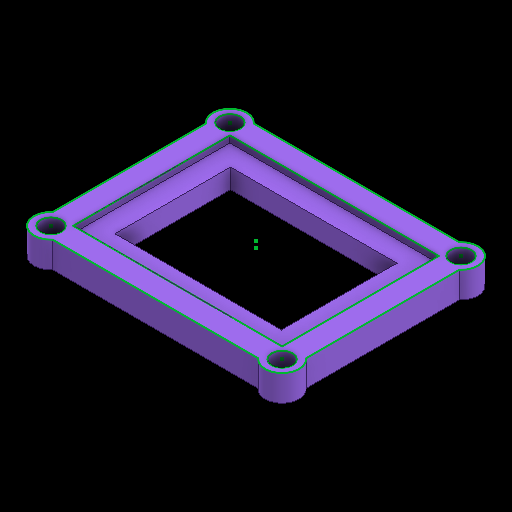
# Autodesk Inventor part: Basisplatte_Gehäuse
Saved by Autodesk Inventor 2027.1 (Build 311270010, 270A)
## iProperties
Created: 2026-10-13
Part Number: Basisplatte_Gehäuse
Material: Generisch
Document SubType Name: Modeling
Designer: josia
Density: 1 g/cm^3
Appearance: Violett
Author: josia
Autodesk Inventor part; units mm, degrees
ref_plane "YZ Plane" through (0, 0, 0) normal (1, 0, 0) x (0, 1, 0)
ref_plane "XZ Plane" through (0, 0, 0) normal (0, 1, 0) x (-1, 0, 0)
ref_plane "XY Plane" through (0, 0, 0) normal (0, 0, 1) x (1, 0, 0)
sketch "Skizze1" plane through (0, 0, 0) normal (0, 1, 0) x (-1, 0, 0)
  line L0 (-16, -12) -> (16, -12)
  line L1 (16, -12) -> (16, 12)
  line L2 (16, 12) -> (-16, 12)
  line L3 (-16, 12) -> (-16, -12)
  line L4 (-16, -12) -> (16, 12) construction
  line L5 (16, -12) -> (-16, 12) construction
  point P0 (0, 0)
  dimension "d0" = 32
  dimension "d1" = 24
  constraints: 12 end point, 2 midpoint, 2 parallel, 1 horizontal, 1 perpendicular
  measures "d0" distance of L2.end L1.end
  measures "d1" distance of L1.end L0.end
extrude "Extrusion1" add sketch "Skizze1" along normal blind 3
sketch "Skizze2" plane through (0, 3, 0) normal (0, 1, 0) x (1, 0, 0)
  point P0 (0, 0)
sketch "Skizze3" plane through (0, 3, 0) normal (0, 1, 0) x (1, 0, 0)
  line L0 (-16, 12) -> (-16, -12) projected
  line L1 (-16, -12) -> (16, -12) projected
  line L2 (16, -12) -> (16, 12) projected
  line L3 (16, 12) -> (-16, 12) projected
  line L4 (19.4, -15.4) -> (-19.4, -15.4)
  line L5 (-19.4, -15.4) -> (-19.4, 15.4)
  line L6 (-19.4, 15.4) -> (19.4, 15.4)
  line L7 (19.4, 15.4) -> (19.4, -15.4)
  point P0 (0, 0)
  dimension "d4" = 3.4
  constraints: 8 end point, 3 other
  measures "d4" distance between parallel lines of L1 L4
extrude "Extrusion2" add sketch "Skizze3" along normal mid plane 6
sketch "Skizze4" plane through (0, 6, 0) normal (0, 1, 0) x (1, 0, 0)
  line L0 (16, -12) -> (-16, -12) projected
  line L1 (19.4, -15.4) -> (19.4, 15.4) projected
  line L2 (16, -12) -> (19.4, -15.4)
  line L3 (19.4, -15.4) -> (19.4, -12)
  line L4 (19.4, -12) -> (16, -15.4)
  circle A0 centre (17.7, -13.7) radius 1.6
  circle A1 centre (17.7, -13.7) radius 2.6
  line L5 (-19.4, -15.4) -> (19.4, -15.4) projected
  line L6 (19.4, -15.4) -> (13.1296, -15.4)
  point P0 (0, 0)
  point P1 (15.7328, -15.4)
  point P2 (19.4, -11.7328)
  point P3 (18.8314, -12.5686)
  point P4 (16.5686, -14.8314)
  dimension "d7" = 3.2
  dimension "d8" = 5.2
  constraints: 8 end point, 2 centre point, 2 point on line, 1 coincident, 1 midpoint, 1 perpendicular
  measures "d7" diameter of A0
  measures "d8" diameter of A1
extrude "Extrusion3" add sketch "Skizze4" against normal blind 6 contours A1 L5 L1 | L4 L1 L2 A0 | A0 L2 L5 L4
sketch "Skizze5" plane through (0, 6, 0) normal (0, 1, 0) x (1, 0, 0)
  line L0 (-16, -12) -> (-16, 12) projected
  line L1 (-19.4, -15.4) -> (-19.4, 15.4) projected
  line L2 (-16, -12) -> (-19.4, -15.4)
  line L3 (-19.4, -15.4) -> (-19.4, -12)
  line L4 (-19.4, -12) -> (-16, -12)
  line L5 (15.7328, -15.4) -> (-19.4, -15.4) projected
  line L6 (-16, -15.4) -> (-19.4, -12)
  line L7 (-16, 12) -> (16, 12) projected
  line L8 (-16, 12) -> (-19.4, 15.4)
  line L9 (-19.4, 15.4) -> (-19.4, 12)
  line L10 (-19.4, 12) -> (-16, 15.4)
  line L11 (-19.4, 15.4) -> (19.4, 15.4) projected
  line L12 (16, 12) -> (19.4, 15.4)
  line L13 (19.4, 15.4) -> (19.4, 12)
  line L14 (19.4, -11.7328) -> (19.4, 15.4) projected
  line L15 (19.4, 12) -> (16, 15.4)
  circle A0 centre (17.7, 13.7) radius 2.1
  circle A1 centre (17.7, 13.7) radius 2.6
  circle A2 centre (-17.7, 13.7) radius 2.6
  circle A3 centre (-17.7, -13.7) radius 2.6
  point P0 (0, 0)
  point P1 (19.4, 11.7328)
  point P2 (15.7328, 15.4)
  point P3 (-15.7328, 15.4)
  point P4 (-19.4, 11.7328)
  point P5 (-19.4, -11.7328)
  point P6 (-15.7328, -15.4)
  dimension "d11" = 4.2
  dimension "d12" = 5.2
  dimension "d13" = 5.2
  dimension "d14" = 5.2
  constraints: 20 end point, 4 centre point, 4 perpendicular, 4 point on line, 3 midpoint, 1 coincident, 1 parallel, 1 vertical
  measures "d11" diameter of A0
  measures "d12" diameter of A1
  measures "d13" diameter of A2
  measures "d14" diameter of A3
extrude "Extrusion4" add sketch "Skizze5" against normal blind 6 contours L1 L5 A3 | A2 L11 L1 | A1 L14 L13 A0 L11 | A0 L11 | L13 A0
sketch "Skizze6" plane through (0, 6, 0) normal (0, 1, 0) x (1, 0, 0)
  line L0 (19.4, -11.7328) -> (19.4, 11.7328) projected
  arc A0 (19.4, 11.7328) -> (15.7328, 15.4) centre (17.7, 13.7) ccw projected
  line L1 (15.7328, 15.4) -> (-15.7328, 15.4) projected
  arc A1 (-15.7328, 15.4) -> (-19.4, 11.7328) centre (-17.7, 13.7) ccw projected
  line L2 (-19.4, 11.7328) -> (-19.4, -11.7328) projected
  arc A2 (-19.4, -11.7328) -> (-15.7328, -15.4) centre (-17.7, -13.7) ccw projected
  line L3 (-15.7328, -15.4) -> (15.7328, -15.4) projected
  arc A3 (15.7328, -15.4) -> (19.4, -11.7328) centre (17.7, -13.7) ccw projected
  line L4 (-16, 12) -> (16, 12) projected
  line L5 (16, 12) -> (16, -12) projected
  line L6 (16, -12) -> (-16, -12) projected
  line L7 (-16, -12) -> (-16, 12) projected
  point P0 (0, 0)
extrude "Extrusion5" cut sketch "Skizze6" against normal blind 2
sketch "Skizze7" plane through (0, 4, 0) normal (0, 1, 0) x (1, 0, 0)
  arc A0 (15.7328, -15.4) -> (19.4, -11.7328) centre (17.7, -13.7) ccw projected
  circle A1 centre (17.7, -13.7) radius 1.6
  arc A2 (-19.4, -11.7328) -> (-15.7328, -15.4) centre (-17.7, -13.7) ccw projected
  circle A3 centre (-17.7, -13.7) radius 1.6
  arc A4 (-15.7328, 15.4) -> (-19.4, 11.7328) centre (-17.7, 13.7) ccw projected
  circle A5 centre (-17.7, 13.7) radius 1.6
  arc A6 (19.4, 11.7328) -> (15.7328, 15.4) centre (17.7, 13.7) ccw projected
  circle A7 centre (17.7, 13.7) radius 1.6
  point P0 (0, 0)
  dimension "d19" = 3.2
  dimension "d20" = 3.2
  dimension "d21" = 3.2
  dimension "d22" = 3.2
  constraints: 4 centre point, 4 coincident
  measures "d19" diameter of A1
  measures "d20" diameter of A3
  measures "d21" diameter of A5
  measures "d22" diameter of A7
extrude "Extrusion6" cut sketch "Skizze7" against normal blind 2.5
sketch "Skizze8" plane through (0, 3, 0) normal (0, 1, 0) x (1, 0, 0)
  line L0 (12.75, -8.85) -> (-12.75, -8.85)
  line L1 (-12.75, -8.85) -> (-12.75, 8.85)
  line L2 (-12.75, 8.85) -> (12.75, 8.85)
  line L3 (12.75, 8.85) -> (12.75, -8.85)
  line L4 (12.75, -8.85) -> (-12.75, 8.85) construction
  line L5 (-12.75, -8.85) -> (12.75, 8.85) construction
  point P0 (0, 0)
  dimension "d25" = 25.5
  dimension "d26" = 17.7
  constraints: 12 end point, 2 midpoint, 2 parallel, 1 horizontal, 1 perpendicular
  measures "d25" distance of L1.end L2.end
  measures "d26" distance between parallel lines of L0 L2
extrude "Extrusion7" cut sketch "Skizze8" against normal blind 6
sketch "Skizze9" plane through (0, 4, 0) normal (0, 1, 0) x (1, 0, 0)
  circle A0 centre (-17.7, 13.7) radius 1.6 projected
  circle A1 centre (-17.7, -13.7) radius 1.6 projected
  circle A2 centre (17.7, 13.7) radius 1.6 projected
  circle A3 centre (17.7, -13.7) radius 1.6 projected
  arc A4 (19.4, 11.7328) -> (15.7328, 15.4) centre (17.7, 13.7) ccw projected
  line L0 (-15.7328, 15.4) -> (15.7328, 15.4) projected
  arc A5 (-15.7328, 15.4) -> (-19.4, 11.7328) centre (-17.7, 13.7) ccw projected
  line L1 (-19.4, -11.7328) -> (-19.4, 11.7328) projected
  arc A6 (-19.4, -11.7328) -> (-15.7328, -15.4) centre (-17.7, -13.7) ccw projected
  line L2 (15.7328, -15.4) -> (-15.7328, -15.4) projected
  arc A7 (15.7328, -15.4) -> (19.4, -11.7328) centre (17.7, -13.7) ccw projected
  line L3 (19.4, 11.7328) -> (19.4, -11.7328) projected
  line L4 (16, 12) -> (-16, 12) projected
  line L5 (16, -12) -> (16, 12) projected
  line L6 (-16, -12) -> (16, -12) projected
  line L7 (-16, 12) -> (-16, -12) projected
  point P0 (0, 0)
